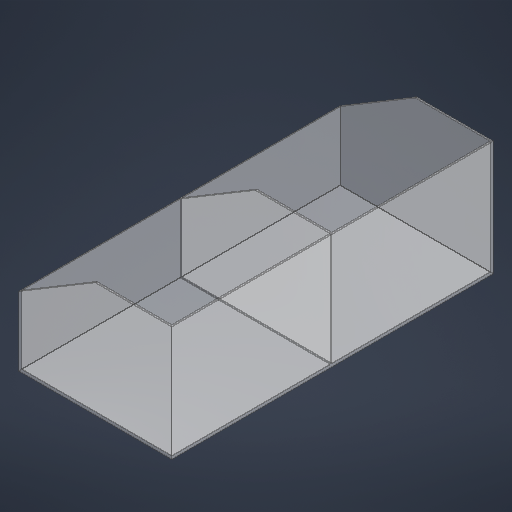
# Autodesk Inventor part: box
Saved by Autodesk Inventor 2026.2 (Build 302298010, 298A)
## iProperties
Created: 2026-03-22
Part Number: box
Material: PET 플라스틱
Document SubType Name: Modeling
Designer: work
Density: 1.541 g/cm^3
Appearance: 폴리카보네이트 - 선명
Author: work
Autodesk Inventor part; units mm, degrees
ref_plane "YZ Plane" through (0, 0, 0) normal (1, 0, 0) x (0, 1, 0)
ref_plane "XZ Plane" through (0, 0, 0) normal (0, 1, 0) x (-1, 0, 0)
ref_plane "XY Plane" through (0, 0, 0) normal (0, 0, 1) x (1, 0, 0)
sketch "스케치1" plane through (0, 0, 0) normal (0, 1, 0) x (-1, 0, 0)
  line L0 (0, 0) -> (200, 0)
  line L1 (200, 0) -> (200, -420)
  line L2 (200, -420) -> (0, -420)
  line L3 (0, -420) -> (0, 0)
  line L4 (200, -210) -> (0, -210) construction
  line L5 (100, 0) -> (100, -420) construction
  line L6 (2, -2) -> (198, -2)
  line L7 (198, -2) -> (198, -418)
  line L8 (198, -418) -> (2, -418)
  line L9 (2, -418) -> (2, -2)
  line L10 (2, -2) -> (198, -418) construction
  line L11 (198, -2) -> (2, -418) construction
  line L12 (198, -209) -> (2, -209)
  line L13 (198, -211) -> (2, -211)
  point P0 (100, -210)
  dimension "d0" = 200
  dimension "d1" = 420
  dimension "d2" = 2
  dimension "d3" = 2
  dimension "d4" = 2
  dimension "d5" = 1
  constraints: 28 end point, 7 midpoint, 5 parallel, 4 point on line, 2 horizontal, 2 perpendicular
  measures "d0" distance of L1.end L2.end
  measures "d1" distance of L0.end L1.end
  measures "d2" distance between parallel lines of L2 L8
  measures "d3" distance between parallel lines of L1 L7
  measures "d4" distance between parallel lines of L13 L12
  measures "d5" distance between parallel lines of L4 L12
extrude "돌출1" add sketch "스케치1" along normal blind 2 contours L6 L7 L12 L9 | L13 L7 L8 L9
extrude "돌출2" add sketch "스케치1" along normal blind 150 contours L0 L1 L2 L3 | L12 L7 L13 L9
sketch "스케치2" plane through (0, 0, -420) normal (0, 0, -1) x (-1, 0, 0)
  line L0 (2, 150) -> (198, 150) projected
  line L1 (100, 150) -> (200, 90)
  line L2 (200, 0) -> (200, 150) projected
  line L3 (0, 0) -> (200, 0) projected
  line L4 (200, 0) -> (200, 150) projected
  line L5 (0, 150) -> (200, 150) projected
  line L6 (0, 0) -> (0, 150) projected
  dimension "d10" = 60
  constraints: 2 end point, 1 midpoint, 1 point on line
  measures "d10" distance of L2.end L1.end
extrude "돌출3" cut sketch "스케치2" against normal through all contours L0 L5 L2 L1
sketch "스케치3" plane through (0, 0, 0) normal (1, 0, 0) x (0, 0, -1)
  line L0 (0, 0) -> (420, 0) projected
  line L1 (420, 0) -> (420, 150) projected
  line L2 (0, 150) -> (420, 150) projected
  line L3 (0, 0) -> (0, 150) projected
  line L4 (210, 150) -> (210, 0) construction
  line L5 (209, 150) -> (209, 91.2) projected
  line L6 (209, 110) -> (0, 110) construction
  line L7 (0, 150) -> (420, 150) projected
  line L8 (24.5, 80) -> (184.5, 80)
  line L9 (184.5, 80) -> (184.5, 140)
  line L10 (184.5, 140) -> (24.5, 140)
  line L11 (24.5, 140) -> (24.5, 80)
  line L12 (24.5, 80) -> (184.5, 140) construction
  line L13 (184.5, 80) -> (24.5, 140) construction
  line L14 (211, 110) -> (420, 110) construction
  line L15 (395.5, 80) -> (235.5, 80)
  line L16 (235.5, 80) -> (235.5, 140)
  line L17 (235.5, 140) -> (395.5, 140)
  line L18 (395.5, 140) -> (395.5, 80)
  line L19 (395.5, 80) -> (235.5, 140) construction
  line L20 (235.5, 80) -> (395.5, 140) construction
  point P0 (104.5, 110)
  point P1 (315.5, 110)
  dimension "d14" = 40
  dimension "d15" = 160
  dimension "d16" = 60
  constraints: 30 end point, 7 symmetric about line, 5 midpoint, 3 parallel, 2 point on line, 1 horizontal, 1 perpendicular
  measures "d14" distance between parallel lines of L2 L6
  measures "d15" distance of L10.end L9.end
  measures "d16" distance of L9.end L8.end
